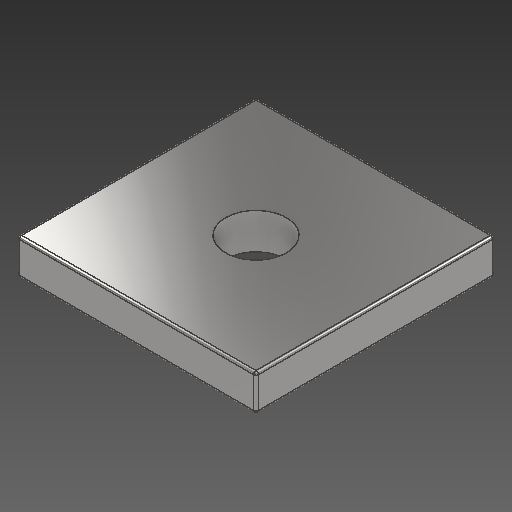
# Autodesk Inventor part: Flange
Saved by Autodesk Inventor 2026.1 (Build 301233020, 233B)
## iProperties
Created: 2026-10-26
Part Number: Flange
Material: Stainless Steel, 440C
Document SubType Name: Modeling
Designer: YmCris
Density: 7.75 g/cm^3
Appearance: Semi-Polished
Author: YmCris
Autodesk Inventor part; units mm, degrees
ref_plane "YZ Plane" through (0, 0, 0) normal (1, 0, 0) x (0, 1, 0)
ref_plane "XZ Plane" through (0, 0, 0) normal (0, 1, 0) x (-1, 0, 0)
ref_plane "XY Plane" through (0, 0, 0) normal (0, 0, 1) x (1, 0, 0)
sketch "Sketch1" plane through (0, 0, 0) normal (0, 1, 0) x (-1, 0, 0)
  point P0 (0, 0)
sketch "Sketch2" plane through (0, 0, 0) normal (0, 1, 0) x (-1, 0, 0)
  line L0 (98, 100) -> (-98, 100)
  line L1 (-100, 98) -> (-100, -98)
  line L2 (-98, -100) -> (100, -100)
  line L3 (100, -100) -> (100, 98)
  arc A0 (100, 98) -> (98, 100) centre (98, 98) ccw
  arc A1 (-98, 100) -> (-100, 98) centre (-98, 98) ccw
  arc A2 (-100, -98) -> (-98, -100) centre (-98, -98) ccw
  point P0 (-100, -100)
  point P1 (-100, 100)
  dimension "d0" = 200
  dimension "d1" = 200
  dimension "d2" = 2
  constraints: 8 end point, 6 point on circle, 6 tangent, 4 point on line, 3 centre point, 2 equal radius, 2 parallel, 1 horizontal, 1 perpendicular
  measures "d0" distance of L2.end point (-100, -100)
  measures "d1" distance of point (-100, -100) point (-100, 100)
  measures "d2" radius of A0
extrude "Extrusion1" add sketch "Sketch2" along normal blind 30
sketch "Sketch3" plane through (0, 30, 0) normal (0, 1, 0) x (1, 0, 0)
  circle A0 centre (0, 0) radius 25.5
  dimension "d5" = 51
  constraints: 1 centre point, 1 coincident
  measures "d5" diameter of A0
extrude "Extrusion2" cut sketch "Sketch3" against normal blind 30
fillet "Fillet1" radius 2 14 edges at (-99.4142, 30, 99.4142) (0, 30, 100) (99.4142, 30, 99.4142) (100, 30, 0) (99.4142, 30, -99.4142) (-1, 30, -100) (-100, 30, -1) (99.4142, 0, 99.4142) (100, 0, 0) (99.4142, 0, -99.4142) (-1, 0, -100) (-99.4142, 0, 99.4142) (-100, 0, -1) (0, 0, 100)
body "Solid1"
